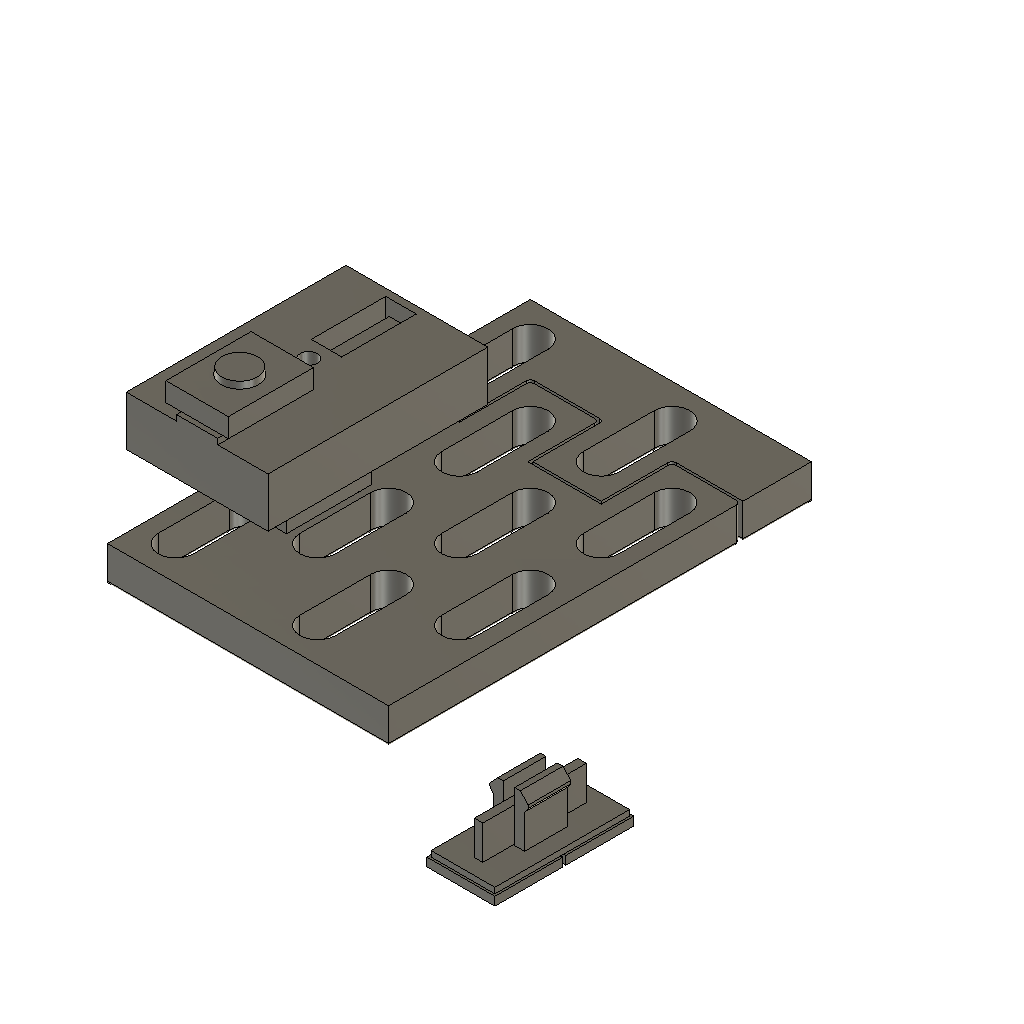
fit-kit-v06 (Autodesk Fusion 360 design; units mm, degrees)
part number: 2026-10-31-20-31-25-279
part number: 2026-10-31-20-31-25-627
part number: 2026-10-31-20-31-26-439
part number: 2026-10-31-20-31-27-406
part number: 2026-10-31-20-31-29-079
part number: 2026-10-31-20-31-30-945
part number: 2026-10-31-20-31-34-959
part number: 2026-10-31-20-31-37-328
part number: 2026-10-31-20-31-45-577
Autodesk Fusion 360 part; units mm, degrees
(part 1 of 2)
sketch "Mount coupon web sketch" plane through (0, 0, 0) normal (0, 0, 1) x (1, 0, 0) in component "Panel mounting coupon"
  line L0 (0.175, 0.175) -> (39.825, 0.175)
  line L1 (39.825, 0.175) -> (39.825, 39.825)
  line L2 (39.825, 39.825) -> (0.175, 39.825)
  line L3 (0.175, 39.825) -> (0.175, 0.175)
  dimension "d67" = 0.175
  dimension "d68" = 0.175
  dimension "d69" = 39.65
  dimension "d70" = 39.65
  constraint horizontal L0
  constraint vertical L1
  constraint horizontal L2
  constraint vertical L3
  measures "d67" horizontal distance of origin L0.start
  measures "d68" vertical distance of origin L0.start
  measures "d69" horizontal distance of L0.start L0.end
  measures "d70" vertical distance of L0.end L1.end
extrude "Mount coupon web" add sketch "Mount coupon web sketch" along normal blind 5 makes body 1 in component "Panel mounting coupon"
sketch "Whole slot seam tooth sketch" plane through (0, 0, 0) normal (0, 0, 1) x (1, 0, 0) in component "Panel mounting coupon"
  line L0 (10.175, 39) -> (19.825, 39)
  line L1 (19.825, 39) -> (19.825, 49.825)
  line L2 (19.825, 49.825) -> (10.175, 49.825)
  line L3 (10.175, 49.825) -> (10.175, 39)
  dimension "d73" = 10.175
  dimension "d74" = 39
  dimension "d75" = 9.65
  dimension "d76" = 10.825
  constraint horizontal L0
  constraint vertical L1
  constraint horizontal L2
  constraint vertical L3
  measures "d73" horizontal distance of origin L0.start
  measures "d74" vertical distance of origin L0.start
  measures "d75" horizontal distance of L0.start L0.end
  measures "d76" vertical distance of L0.end L1.end
extrude "Whole slot seam tooth" add sketch "Whole slot seam tooth sketch" along normal blind 5 bodies 1 in component "Panel mounting coupon"
fillet "Rounded tooth seed" radius 0.6 2 edges at (19.825, 49.825, 2.5) (10.175, 49.825, 2.5) on bodies 1 in component "Panel mounting coupon"
pattern_linear "Two teeth" count 2 spacing 20 along (1, 0, 0) of "Whole slot seam tooth", "Rounded tooth seed" in component "Panel mounting coupon"
sketch "A slots constrained seed" plane through (0, 0, 0) normal (0, 0, 1) x (1, 0, 0) in component "Panel mounting coupon"
  line L0 (7.5, 5) -> (7.5, 15)
  arc A0 (7.5, 15) -> (2.5, 15) centre (5, 15) ccw
  line L1 (2.5, 15) -> (2.5, 5)
  arc A1 (2.5, 5) -> (7.5, 5) centre (5, 5) ccw
  line L2 (5, 5) -> (5, 15) construction
  line L3 (5, 5) -> (15, 5) construction
  dimension "d85" = 5
  dimension "d86" = 10
  dimension "d87" = 90
  dimension "d88" = 10
  dimension "d89" = 5
  dimension "d90" = 5
  constraint tangent L0 A0
  constraint tangent A0 L1
  constraint tangent L1 A1
  constraint tangent L0 A1
  constraint parallel L0 L1
  constraint horizontal L3
  measures "d85" diameter of A0
  measures "d86" distance of A1.centre A0.centre
  measures "d87" angle of L2 L3
  measures "d88" horizontal distance of A1.centre L3.end
  measures "d89" horizontal distance of origin A1.centre
  measures "d90" vertical distance of origin A1.centre
extrude "A slots through cut" cut sketch "A slots constrained seed" along normal blind 5 bodies 1 in component "Panel mounting coupon"
pattern_linear "A slots lattice" count 2 spacing 20 along (1, 0, 0) count 2 spacing 20 along (0, 1, 0) of "A slots through cut" in component "Panel mounting coupon"
sketch "B slots including seam constrained seed" plane through (0, 0, 0) normal (0, 0, 1) x (1, 0, 0) in component "Panel mounting coupon"
  line L0 (17.5, 15) -> (17.5, 25)
  arc A0 (17.5, 25) -> (12.5, 25) centre (15, 25) ccw
  line L1 (12.5, 25) -> (12.5, 15)
  arc A1 (12.5, 15) -> (17.5, 15) centre (15, 15) ccw
  line L2 (15, 15) -> (15, 25) construction
  line L3 (15, 15) -> (25, 15) construction
  dimension "d97" = 5
  dimension "d98" = 10
  dimension "d99" = 90
  dimension "d100" = 10
  dimension "d101" = 15
  dimension "d102" = 15
  constraint tangent L0 A0
  constraint tangent A0 L1
  constraint tangent L1 A1
  constraint tangent L0 A1
  constraint parallel L0 L1
  constraint horizontal L3
  measures "d97" diameter of A0
  measures "d98" distance of A1.centre A0.centre
  measures "d99" angle of L2 L3
  measures "d100" horizontal distance of A1.centre L3.end
  measures "d101" horizontal distance of origin A1.centre
  measures "d102" vertical distance of origin A1.centre
extrude "B slots including seam through cut" cut sketch "B slots including seam constrained seed" along normal blind 5 bodies 1 in component "Panel mounting coupon"
pattern_linear "B slots including seam lattice" count 2 spacing 20 along (1, 0, 0) count 2 spacing 20 along (0, 1, 0) of "B slots including seam through cut" in component "Panel mounting coupon"
fillet "Production slot and perimeter rounding" radius 0.4 2 faces at (34.0461, 5.894, 0) (34.0461, 5.894, 0) on bodies 1 in component "Panel mounting coupon"
sketch "11 M2 through bore sketch" plane through (0, 0, 0) normal (0, 0, 1) x (1, 0, 0) in component "Panel mounting coupon"
  circle A0 centre (8.75, 20) radius 1.2
  dimension "d111" = 8.75
  dimension "d112" = 20
  dimension "d113" = 2.4
  measures "d111" horizontal distance of origin A0.centre
  measures "d112" vertical distance of origin A0.centre
  measures "d113" diameter of A0
extrude "11 M2 through bore" cut sketch "11 M2 through bore sketch" along normal blind 5 bodies 1 in component "Panel mounting coupon"
sketch "12 Flush countersink sketch" plane through (0, 0, 0) normal (0, 0, 1) x (1, 0, 0) in component "Panel mounting coupon"
  circle A0 centre (8.75, 20) radius 2
  dimension "d116" = 8.75
  dimension "d117" = 20
  dimension "d118" = 4
  measures "d116" horizontal distance of origin A0.centre
  measures "d117" vertical distance of origin A0.centre
  measures "d118" diameter of A0
extrude "12 Flush countersink" cut sketch "12 Flush countersink sketch" along normal blind 0.8 draft -45 bodies 1 in component "Panel mounting coupon"
ref_plane "WorkPlane1" through (0, 0, 5) normal (0, 0, 1) x (1, 0, 0) in component "Panel mounting coupon"
sketch "Blind rear production registration sketch" plane through (0, 0, 5) normal (0, 0, 1) x (1, 0, 0) in component "Panel mounting coupon"
  line L0 (8.4, 15.8) -> (11.6, 15.8)
  line L1 (11.6, 15.8) -> (11.6, 24.2)
  line L2 (11.6, 24.2) -> (8.4, 24.2)
  line L3 (8.4, 24.2) -> (8.4, 15.8)
  dimension "d123" = 8.4
  dimension "d124" = 15.8
  dimension "d125" = 3.2
  dimension "d126" = 8.4
  constraint horizontal L0
  constraint vertical L1
  constraint horizontal L2
  constraint vertical L3
  measures "d123" horizontal distance of origin L0.start
  measures "d124" vertical distance of origin L0.start
  measures "d125" horizontal distance of L0.start L0.end
  measures "d126" vertical distance of L0.end L1.end
extrude "Blind rear production registration" cut sketch "Blind rear production registration sketch" against normal blind 0.8 bodies 1 in component "Panel mounting coupon"
sketch "Small seam mate web sketch" plane through (0, 0, 0) normal (0, 0, 1) x (1, 0, 0) in component "PRINT seam mate"
  line L0 (0.175, 40.175) -> (39.825, 40.175)
  line L1 (39.825, 40.175) -> (39.825, 59.825)
  line L2 (39.825, 59.825) -> (0.175, 59.825)
  line L3 (0.175, 59.825) -> (0.175, 40.175)
  dimension "d129" = 0.175
  dimension "d130" = 40.175
  dimension "d131" = 39.65
  dimension "d132" = 19.65
  constraint horizontal L0
  constraint vertical L1
  constraint horizontal L2
  constraint vertical L3
  measures "d129" horizontal distance of origin L0.start
  measures "d130" vertical distance of origin L0.start
  measures "d131" horizontal distance of L0.start L0.end
  measures "d132" vertical distance of L0.end L1.end
extrude "Small seam mate web" add sketch "Small seam mate web sketch" along normal blind 5 separate body makes body 2 in component "PRINT seam mate"
sketch "Receiving step sketch" plane through (0, 0, 0) normal (0, 0, 1) x (1, 0, 0) in component "PRINT seam mate"
  line L0 (9.825, 39) -> (20.175, 39)
  line L1 (20.175, 39) -> (20.175, 50.175)
  line L2 (20.175, 50.175) -> (9.825, 50.175)
  line L3 (9.825, 50.175) -> (9.825, 39)
  dimension "d135" = 9.825
  dimension "d136" = 39
  dimension "d137" = 10.35
  dimension "d138" = 11.175
  constraint horizontal L0
  constraint vertical L1
  constraint horizontal L2
  constraint vertical L3
  measures "d135" horizontal distance of origin L0.start
  measures "d136" vertical distance of origin L0.start
  measures "d137" horizontal distance of L0.start L0.end
  measures "d138" vertical distance of L0.end L1.end
extrude "Receiving step" cut sketch "Receiving step sketch" along normal blind 5 bodies 2 in component "PRINT seam mate"
fillet "Rounded receiving step" radius 0.6 2 edges at (20.175, 50.175, 2.5) (9.825, 50.175, 2.5) on bodies 2 in component "PRINT seam mate"
sketch "Receiving step sketch (1)" plane through (0, 0, 0) normal (0, 0, 1) x (1, 0, 0) in component "PRINT seam mate"
  line L0 (29.825, 39) -> (40.175, 39)
  line L1 (40.175, 39) -> (40.175, 50.175)
  line L2 (40.175, 50.175) -> (29.825, 50.175)
  line L3 (29.825, 50.175) -> (29.825, 39)
  dimension "d143" = 29.825
  dimension "d144" = 39
  dimension "d145" = 10.35
  dimension "d146" = 11.175
  constraint horizontal L0
  constraint vertical L1
  constraint horizontal L2
  constraint vertical L3
  measures "d143" horizontal distance of origin L0.start
  measures "d144" vertical distance of origin L0.start
  measures "d145" horizontal distance of L0.start L0.end
  measures "d146" vertical distance of L0.end L1.end
extrude "Receiving step (1)" cut sketch "Receiving step sketch (1)" along normal blind 5 bodies 2 in component "PRINT seam mate"
fillet "Rounded receiving step (1)" radius 0.6 1 edges at (29.825, 50.175, 2.5) on bodies 2 in component "PRINT seam mate"
sketch "Whole A slots constrained seed" plane through (0, 0, 0) normal (0, 0, 1) x (1, 0, 0) in component "PRINT seam mate"
  line L0 (7.5, 45) -> (7.5, 55)
  arc A0 (7.5, 55) -> (2.5, 55) centre (5, 55) ccw
  line L1 (2.5, 55) -> (2.5, 45)
  arc A1 (2.5, 45) -> (7.5, 45) centre (5, 45) ccw
  line L2 (5, 45) -> (5, 55) construction
  line L3 (5, 45) -> (15, 45) construction
  dimension "d151" = 5
  dimension "d152" = 10
  dimension "d153" = 90
  dimension "d154" = 10
  dimension "d155" = 5
  dimension "d156" = 45
  constraint tangent L0 A0
  constraint tangent A0 L1
  constraint tangent L1 A1
  constraint tangent L0 A1
  constraint parallel L0 L1
  constraint horizontal L3
  measures "d151" diameter of A0
  measures "d152" distance of A1.centre A0.centre
  measures "d153" angle of L2 L3
  measures "d154" horizontal distance of A1.centre L3.end
  measures "d155" horizontal distance of origin A1.centre
  measures "d156" vertical distance of origin A1.centre
extrude "Whole A slots through cut" cut sketch "Whole A slots constrained seed" along normal blind 5 bodies 2 in component "PRINT seam mate"
pattern_linear "Whole A slots lattice" count 2 spacing 20 along (1, 0, 0) of "Whole A slots through cut" in component "PRINT seam mate"
fillet "Production slot and perimeter rounding'" radius 0.4 2 faces at (36.6917, 53.3917, 0) (36.6917, 53.3917, 0) on bodies 2 in component "PRINT seam mate"
ref_plane "WorkPlane1" through (0, 0, 15) normal (0, 0, 1) x (1, 0, 0) in component "PRINT carrier 00 single"
sketch "Carrier bearing block sketch" plane through (0, 0, 15) normal (0, 0, 1) x (1, 0, 0) in component "PRINT carrier 00 single"
  line L0 (0, 3) -> (20, 3)
  line L1 (20, 3) -> (20, 34)
  line L2 (20, 34) -> (0, 34)
  line L3 (0, 34) -> (0, 3)
  dimension "d167" = 3
  dimension "d168" = 20
  dimension "d169" = 31
  constraint horizontal L0
  constraint vertical L1
  constraint horizontal L2
  constraint vertical L3
  constraint vertical origin L0.start
  measures "d167" vertical distance of origin L0.start
  measures "d168" horizontal distance of L0.start L0.end
  measures "d169" vertical distance of L0.end L1.end
extrude "Carrier bearing block" add sketch "Carrier bearing block sketch" along normal blind 7 separate body makes body 3 in component "PRINT carrier 00 single"
ref_plane "WorkPlane2" through (0, 0, 15) normal (0, 0, 1) x (1, 0, 0) in component "PRINT carrier 00 single"
sketch "Integrated compression blade sketch" plane through (0, 0, 15) normal (0, 0, 1) x (1, 0, 0) in component "PRINT carrier 00 single"
  line L0 (8.4, 14) -> (11.6, 14)
  line L1 (11.6, 14) -> (11.6, 26)
  line L2 (11.6, 26) -> (8.4, 26)
  line L3 (8.4, 26) -> (8.4, 14)
  dimension "d174" = 8.4
  dimension "d175" = 14
  dimension "d176" = 3.2
  dimension "d177" = 12
  constraint horizontal L0
  constraint vertical L1
  constraint horizontal L2
  constraint vertical L3
  measures "d174" horizontal distance of origin L0.start
  measures "d175" vertical distance of origin L0.start
  measures "d176" horizontal distance of L0.start L0.end
  measures "d177" vertical distance of L0.end L1.end
extrude "Integrated compression blade" add sketch "Integrated compression blade sketch" against normal blind 10 bodies 3 in component "PRINT carrier 00 single"
ref_plane "WorkPlane3" through (0, 0, 5) normal (0, 0, 1) x (1, 0, 0) in component "PRINT carrier 00 single"
sketch "Axially releasing registration tongue sketch" plane through (0, 0, 5) normal (0, 0, 1) x (1, 0, 0) in component "PRINT carrier 00 single"
  line L0 (8.6, 16) -> (11.4, 16)
  line L1 (11.4, 16) -> (11.4, 24)
  line L2 (11.4, 24) -> (8.6, 24)
  line L3 (8.6, 24) -> (8.6, 16)
  dimension "d182" = 8.6
  dimension "d183" = 16
  dimension "d184" = 2.8
  dimension "d185" = 8
  constraint horizontal L0
  constraint vertical L1
  constraint horizontal L2
  constraint vertical L3
  measures "d182" horizontal distance of origin L0.start
  measures "d183" vertical distance of origin L0.start
  measures "d184" horizontal distance of L0.start L0.end
  measures "d185" vertical distance of L0.end L1.end
extrude "Axially releasing registration tongue" add sketch "Axially releasing registration tongue sketch" against normal blind 0.6 bodies 3 in component "PRINT carrier 00 single"
ref_plane "WorkPlane4" through (0, 0, 4.4) normal (0, 0, 1) x (1, 0, 0) in component "PRINT carrier 00 single"
sketch "Split registration into printable end pads sketch" plane through (0, 0, 4.4) normal (0, 0, 1) x (1, 0, 0) in component "PRINT carrier 00 single"
  line L0 (8.6, 18) -> (11.4, 18)
  line L1 (11.4, 18) -> (11.4, 22)
  line L2 (11.4, 22) -> (8.6, 22)
  line L3 (8.6, 22) -> (8.6, 18)
  dimension "d190" = 8.6
  dimension "d191" = 18
  dimension "d192" = 2.8
  dimension "d193" = 4
  constraint horizontal L0
  constraint vertical L1
  constraint horizontal L2
  constraint vertical L3
  measures "d190" horizontal distance of origin L0.start
  measures "d191" vertical distance of origin L0.start
  measures "d192" horizontal distance of L0.start L0.end
  measures "d193" vertical distance of L0.end L1.end
extrude "Split registration into printable end pads" cut sketch "Split registration into printable end pads sketch" along normal blind 0.6 bodies 3 in component "PRINT carrier 00 single"
ref_plane "WorkPlane5" through (0, 0, 4.4) normal (0, 0, 1) x (1, 0, 0) in component "PRINT carrier 00 single"
sketch "M2 through passage sketch" plane through (0, 0, 4.4) normal (0, 0, 1) x (1, 0, 0) in component "PRINT carrier 00 single"
  circle A0 centre (8.75, 20) radius 1.2
  dimension "d198" = 8.75
  dimension "d199" = 20
  dimension "d200" = 2.4
  measures "d198" horizontal distance of origin A0.centre
  measures "d199" vertical distance of origin A0.centre
  measures "d200" diameter of A0
extrude "M2 through passage" cut sketch "M2 through passage sketch" along normal blind 17.6 bodies 3 in component "PRINT carrier 00 single"
ref_plane "WorkPlane6" through (0, 0, 17) normal (0, 0, 1) x (1, 0, 0) in component "PRINT carrier 00 single"
sketch "Top-loaded captive hex nut track sketch" plane through (0, 0, 17) normal (0, 0, 1) x (1, 0, 0) in component "PRINT carrier 00 single"
  line L0 (6.6, 17.6) -> (10.9, 17.6)
  line L1 (10.9, 17.6) -> (10.9, 34)
  line L2 (10.9, 34) -> (6.6, 34)
  line L3 (6.6, 34) -> (6.6, 17.6)
  dimension "d205" = 6.6
  dimension "d206" = 17.6
  dimension "d207" = 4.3
  dimension "d208" = 16.4
  constraint horizontal L0
  constraint vertical L1
  constraint horizontal L2
  constraint vertical L3
  measures "d205" horizontal distance of origin L0.start
  measures "d206" vertical distance of origin L0.start
  measures "d207" horizontal distance of L0.start L0.end
  measures "d208" vertical distance of L0.end L1.end
extrude "Top-loaded captive hex nut track" cut sketch "Top-loaded captive hex nut track sketch" along normal blind 2 bodies 3 in component "PRINT carrier 00 single"
ref_plane "WorkPlane1" through (0, 0, 17.2) normal (0, 0, 1) x (1, 0, 0) in component "METAL M2 nut 000"
sketch "M2 hex nut AF4 envelope sketch" plane through (0, 0, 17.2) normal (0, 0, 1) x (1, 0, 0) in component "METAL M2 nut 000"
  line L0 (10.75, 21.1547) -> (8.75, 22.3094)
  line L1 (8.75, 22.3094) -> (6.75, 21.1547)
  line L2 (6.75, 21.1547) -> (6.75, 18.8453)
  line L3 (6.75, 18.8453) -> (8.75, 17.6906)
  line L4 (8.75, 17.6906) -> (10.75, 18.8453)
  line L5 (10.75, 18.8453) -> (10.75, 21.1547)
  dimension "d213" = 10.75
  dimension "d214" = 21.1547
  dimension "d215" = 8.75
  dimension "d216" = 22.3094
  dimension "d217" = 6.75
  dimension "d218" = 18.8453
  dimension "d219" = 8.75
  dimension "d220" = 17.6906
  constraint horizontal L0.start L1.end
  constraint vertical L1.end L2.end
  constraint vertical L0.start L4.end
  constraint horizontal L2.end L4.end
  measures "d213" horizontal distance of origin L0.start
  measures "d214" vertical distance of origin L0.start
  measures "d215" horizontal distance of origin L0.end
  measures "d216" vertical distance of origin L0.end
  measures "d217" horizontal distance of origin L1.end
  measures "d218" vertical distance of origin L2.end
  measures "d219" horizontal distance of origin L3.end
  measures "d220" vertical distance of origin L3.end
extrude "M2 hex nut AF4 envelope" add sketch "M2 hex nut AF4 envelope sketch" along normal blind 1.6 separate body makes body 4 in component "METAL M2 nut 000"
ref_plane "WorkPlane2" through (0, 0, 17.2) normal (0, 0, 1) x (1, 0, 0) in component "METAL M2 nut 000"
sketch "Thread envelope sketch" plane through (0, 0, 17.2) normal (0, 0, 1) x (1, 0, 0) in component "METAL M2 nut 000"
  circle A0 centre (8.75, 20) radius 1.05
  dimension "d225" = 8.75
  dimension "d226" = 20
  dimension "d227" = 2.1
  measures "d225" horizontal distance of origin A0.centre
  measures "d226" vertical distance of origin A0.centre
  measures "d227" diameter of A0
extrude "Thread envelope" cut sketch "Thread envelope sketch" along normal blind 1.6 bodies 4 in component "METAL M2 nut 000"
ref_plane "WorkPlane1" through (0, 0, 0.1) normal (0, 0, 1) x (1, 0, 0) in component "REFERENCE panel M2x20 000"
sketch "Nominal 90 degree head sketch" plane through (0, 0, 0.1) normal (0, 0, 1) x (1, 0, 0) in component "REFERENCE panel M2x20 000"
  circle A0 centre (8.75, 20) radius 1.9
  dimension "d248" = 8.75
  dimension "d249" = 20
  dimension "d250" = 3.8
  measures "d248" horizontal distance of origin A0.centre
  measures "d249" vertical distance of origin A0.centre
  measures "d250" diameter of A0
extrude "Nominal 90 degree head" add sketch "Nominal 90 degree head sketch" along normal blind 0.9 draft -45 separate body makes body 5 in component "REFERENCE panel M2x20 000"
ref_plane "WorkPlane2" through (0, 0, 1) normal (0, 0, 1) x (1, 0, 0) in component "REFERENCE panel M2x20 000"
sketch "Unthreaded major-diameter envelope sketch" plane through (0, 0, 1) normal (0, 0, 1) x (1, 0, 0) in component "REFERENCE panel M2x20 000"
  circle A0 centre (8.75, 20) radius 1
  dimension "d255" = 8.75
  dimension "d256" = 20
  dimension "d257" = 2
  measures "d255" horizontal distance of origin A0.centre
  measures "d256" vertical distance of origin A0.centre
  measures "d257" diameter of A0
extrude "Unthreaded major-diameter envelope" add sketch "Unthreaded major-diameter envelope sketch" along normal blind 19.1 bodies 5 in component "REFERENCE panel M2x20 000"
ref_plane "WorkPlane3" through (0, 0, 0.1) normal (0, 0, 1) x (1, 0, 0) in component "REFERENCE panel M2x20 000"
sketch "Cross drive envelope sketch" plane through (0, 0, 0.1) normal (0, 0, 1) x (1, 0, 0) in component "REFERENCE panel M2x20 000"
  line L0 (8.475, 18.86) -> (9.025, 18.86)
  line L1 (9.025, 18.86) -> (9.025, 21.14)
  line L2 (9.025, 21.14) -> (8.475, 21.14)
  line L3 (8.475, 21.14) -> (8.475, 18.86)
  dimension "d262" = 8.475
  dimension "d263" = 18.86
  dimension "d264" = 0.55
  dimension "d265" = 2.28
  constraint horizontal L0
  constraint vertical L1
  constraint horizontal L2
  constraint vertical L3
  measures "d262" horizontal distance of origin L0.start
  measures "d263" vertical distance of origin L0.start
  measures "d264" horizontal distance of L0.start L0.end
  measures "d265" vertical distance of L0.end L1.end
extrude "Cross drive envelope" cut sketch "Cross drive envelope sketch" along normal blind 0.35 bodies 5 in component "REFERENCE panel M2x20 000"
ref_plane "WorkPlane4" through (0, 0, 0.1) normal (0, 0, 1) x (1, 0, 0) in component "REFERENCE panel M2x20 000"
sketch "Cross drive envelope sketch (1)" plane through (0, 0, 0.1) normal (0, 0, 1) x (1, 0, 0) in component "REFERENCE panel M2x20 000"
  line L0 (7.61, 19.725) -> (9.89, 19.725)
  line L1 (9.89, 19.725) -> (9.89, 20.275)
  line L2 (9.89, 20.275) -> (7.61, 20.275)
  line L3 (7.61, 20.275) -> (7.61, 19.725)
  dimension "d270" = 7.61
  dimension "d271" = 19.725
  dimension "d272" = 2.28
  dimension "d273" = 0.55
  constraint horizontal L0
  constraint vertical L1
  constraint horizontal L2
  constraint vertical L3
  measures "d270" horizontal distance of origin L0.start
  measures "d271" vertical distance of origin L0.start
  measures "d272" horizontal distance of L0.start L0.end
  measures "d273" vertical distance of L0.end L1.end
extrude "Cross drive envelope (1)" cut sketch "Cross drive envelope sketch (1)" along normal blind 0.35 bodies 5 in component "REFERENCE panel M2x20 000"
ref_plane "WorkPlane7" through (0, 0, 22) normal (0, 0, 1) x (1, 0, 0) in component "PRINT carrier 00 single"
sketch "Extrusion mouth anti-rotation key sketch" plane through (0, 0, 22) normal (0, 0, 1) x (1, 0, 0) in component "PRINT carrier 00 single"
  line L0 (7.1, 3) -> (12.9, 3)
  line L1 (12.9, 3) -> (12.9, 5)
  line L2 (12.9, 5) -> (7.1, 5)
  line L3 (7.1, 5) -> (7.1, 3)
  dimension "d278" = 7.1
  dimension "d279" = 3
  dimension "d280" = 5.8
  dimension "d281" = 2
  constraint horizontal L0
  constraint vertical L1
  constraint horizontal L2
  constraint vertical L3
  measures "d278" horizontal distance of origin L0.start
  measures "d279" vertical distance of origin L0.start
  measures "d280" horizontal distance of L0.start L0.end
  measures "d281" vertical distance of L0.end L1.end
extrude "Extrusion mouth anti-rotation key" add sketch "Extrusion mouth anti-rotation key sketch" along normal blind 0.8 bodies 3 in component "PRINT carrier 00 single"
ref_plane "WorkPlane8" through (0, 0, 22) normal (0, 0, 1) x (1, 0, 0) in component "PRINT carrier 00 single"
sketch "Extrusion mouth anti-rotation key sketch (1)" plane through (0, 0, 22) normal (0, 0, 1) x (1, 0, 0) in component "PRINT carrier 00 single"
  line L0 (7.1, 13) -> (12.9, 13)
  line L1 (12.9, 13) -> (12.9, 15)
  line L2 (12.9, 15) -> (7.1, 15)
  line L3 (7.1, 15) -> (7.1, 13)
  dimension "d286" = 7.1
  dimension "d287" = 13
  dimension "d288" = 5.8
  dimension "d289" = 2
  constraint horizontal L0
  constraint vertical L1
  constraint horizontal L2
  constraint vertical L3
  measures "d286" horizontal distance of origin L0.start
  measures "d287" vertical distance of origin L0.start
  measures "d288" horizontal distance of L0.start L0.end
  measures "d289" vertical distance of L0.end L1.end
extrude "Extrusion mouth anti-rotation key (1)" add sketch "Extrusion mouth anti-rotation key sketch (1)" along normal blind 0.8 bodies 3 in component "PRINT carrier 00 single"
ref_plane "WorkPlane9" through (0, 0, 15) normal (0, 0, 1) x (1, 0, 0) in component "PRINT carrier 00 single"
sketch "Carrier M5 bore sketch" plane through (0, 0, 15) normal (0, 0, 1) x (1, 0, 0) in component "PRINT carrier 00 single"
  circle A0 centre (10, 9) radius 2.75
  dimension "d294" = 10
  dimension "d295" = 9
  dimension "d296" = 5.5
  measures "d294" horizontal distance of origin A0.centre
  measures "d295" vertical distance of origin A0.centre
  measures "d296" diameter of A0
extrude "Carrier M5 bore" cut sketch "Carrier M5 bore sketch" along normal blind 7 bodies 3 in component "PRINT carrier 00 single"
ref_plane "WorkPlane10" through (0, 0, 15) normal (0, 0, 1) x (1, 0, 0) in component "PRINT carrier 00 single"
sketch "Recessed carrier fixing sketch" plane through (0, 0, 15) normal (0, 0, 1) x (1, 0, 0) in component "PRINT carrier 00 single"
  circle A0 centre (10, 9) radius 4.7
  dimension "d301" = 10
  dimension "d302" = 9
  dimension "d303" = 9.4
  measures "d301" horizontal distance of origin A0.centre
  measures "d302" vertical distance of origin A0.centre
  measures "d303" diameter of A0
extrude "Recessed carrier fixing" cut sketch "Recessed carrier fixing sketch" along normal blind 1.95 draft -45 bodies 3 in component "PRINT carrier 00 single"
ref_plane "WorkPlane1" through (0, 0, 15.1) normal (0, 0, 1) x (1, 0, 0) in component "REFERENCE carrier M5x12 00"
sketch "Nominal 90 degree head sketch (2)" plane through (0, 0, 15.1) normal (0, 0, 1) x (1, 0, 0) in component "REFERENCE carrier M5x12 00"
  circle A0 centre (10, 9) radius 4.6
  dimension "d308" = 10
  dimension "d309" = 9
  dimension "d310" = 9.2
  measures "d308" horizontal distance of origin A0.centre
  measures "d309" vertical distance of origin A0.centre
  measures "d310" diameter of A0
extrude "Nominal 90 degree head'" add sketch "Nominal 90 degree head sketch (2)" along normal blind 2.1 draft -45 separate body makes body 6 in component "REFERENCE carrier M5x12 00"
ref_plane "WorkPlane2" through (0, 0, 17.2) normal (0, 0, 1) x (1, 0, 0) in component "REFERENCE carrier M5x12 00"
sketch "Unthreaded major-diameter envelope sketch (2)" plane through (0, 0, 17.2) normal (0, 0, 1) x (1, 0, 0) in component "REFERENCE carrier M5x12 00"
  circle A0 centre (10, 9) radius 2.5
  dimension "d315" = 10
  dimension "d316" = 9
  dimension "d317" = 5
  measures "d315" horizontal distance of origin A0.centre
  measures "d316" vertical distance of origin A0.centre
  measures "d317" diameter of A0
extrude "Unthreaded major-diameter envelope'" add sketch "Unthreaded major-diameter envelope sketch (2)" along normal blind 9.9 bodies 6 in component "REFERENCE carrier M5x12 00"
ref_plane "WorkPlane3" through (0, 0, 15.1) normal (0, 0, 1) x (1, 0, 0) in component "REFERENCE carrier M5x12 00"
sketch "Cross drive envelope sketch (2)" plane through (0, 0, 15.1) normal (0, 0, 1) x (1, 0, 0) in component "REFERENCE carrier M5x12 00"
  line L0 (9.725, 6.24) -> (10.275, 6.24)
  line L1 (10.275, 6.24) -> (10.275, 11.76)
  line L2 (10.275, 11.76) -> (9.725, 11.76)
  line L3 (9.725, 11.76) -> (9.725, 6.24)
  dimension "d322" = 9.725
  dimension "d323" = 6.24
  dimension "d324" = 0.55
  dimension "d325" = 5.52
  constraint horizontal L0
  constraint vertical L1
  constraint horizontal L2
  constraint vertical L3
  measures "d322" horizontal distance of origin L0.start
  measures "d323" vertical distance of origin L0.start
  measures "d324" horizontal distance of L0.start L0.end
  measures "d325" vertical distance of L0.end L1.end
extrude "Cross drive envelope'" cut sketch "Cross drive envelope sketch (2)" along normal blind 0.35 bodies 6 in component "REFERENCE carrier M5x12 00"
ref_plane "WorkPlane4" through (0, 0, 15.1) normal (0, 0, 1) x (1, 0, 0) in component "REFERENCE carrier M5x12 00"
sketch "Cross drive envelope sketch (1) (2)" plane through (0, 0, 15.1) normal (0, 0, 1) x (1, 0, 0) in component "REFERENCE carrier M5x12 00"
  line L0 (7.24, 8.725) -> (12.76, 8.725)
  line L1 (12.76, 8.725) -> (12.76, 9.275)
  line L2 (12.76, 9.275) -> (7.24, 9.275)
  line L3 (7.24, 9.275) -> (7.24, 8.725)
  dimension "d330" = 7.24
  dimension "d331" = 8.725
  dimension "d332" = 5.52
  dimension "d333" = 0.55
  constraint horizontal L0
  constraint vertical L1
  constraint horizontal L2
  constraint vertical L3
  measures "d330" horizontal distance of origin L0.start
  measures "d331" vertical distance of origin L0.start
  measures "d332" horizontal distance of L0.start L0.end
  measures "d333" vertical distance of L0.end L1.end
extrude "Cross drive envelope (1)'" cut sketch "Cross drive envelope sketch (1) (2)" along normal blind 0.35 bodies 6 in component "REFERENCE carrier M5x12 00"
ref_plane "WorkPlane1" through (0, 0, 23.5) normal (0, 0, 1) x (1, 0, 0) in component "METAL channel nut 00"
sketch "Provisional metal channel nut sketch" plane through (0, 0, 23.5) normal (0, 0, 1) x (1, 0, 0) in component "METAL channel nut 00"
  line L0 (5.6, 3) -> (14.4, 3)
  line L1 (14.4, 3) -> (14.4, 15)
  line L2 (14.4, 15) -> (5.6, 15)
  line L3 (5.6, 15) -> (5.6, 3)
  dimension "d338" = 5.6
  dimension "d339" = 3
  dimension "d340" = 8.8
  dimension "d341" = 12
  constraint horizontal L0
  constraint vertical L1
  constraint horizontal L2
  constraint vertical L3
  measures "d338" horizontal distance of origin L0.start
  measures "d339" vertical distance of origin L0.start
  measures "d340" horizontal distance of L0.start L0.end
  measures "d341" vertical distance of L0.end L1.end
extrude "Provisional metal channel nut" add sketch "Provisional metal channel nut sketch" along normal blind 2.7 separate body makes body 7 in component "METAL channel nut 00"
ref_plane "WorkPlane2" through (0, 0, 23.5) normal (0, 0, 1) x (1, 0, 0) in component "METAL channel nut 00"
sketch "Thread envelope sketch (2)" plane through (0, 0, 23.5) normal (0, 0, 1) x (1, 0, 0) in component "METAL channel nut 00"
  circle A0 centre (10, 9) radius 2.6
  dimension "d346" = 10
  dimension "d347" = 9
  dimension "d348" = 5.2
  measures "d346" horizontal distance of origin A0.centre
  measures "d347" vertical distance of origin A0.centre
  measures "d348" diameter of A0
extrude "Thread envelope'" cut sketch "Thread envelope sketch (2)" along normal blind 2.7 bodies 7 in component "METAL channel nut 00"
ref_plane "WorkPlane11" through (0, 0, 19) normal (0, 0, 1) x (1, 0, 0) in component "PRINT carrier 00 single"
sketch "Release free end of nut-retaining spring sketch" plane through (0, 0, 19) normal (0, 0, 1) x (1, 0, 0) in component "PRINT carrier 00 single"
  line L0 (6.6, 22.5) -> (10.9, 22.5)
  line L1 (10.9, 22.5) -> (10.9, 23)
  line L2 (10.9, 23) -> (6.6, 23)
  line L3 (6.6, 23) -> (6.6, 22.5)
  dimension "d353" = 6.6
  dimension "d354" = 22.5
  dimension "d355" = 4.3
  dimension "d356" = 0.5
  constraint horizontal L0
  constraint vertical L1
  constraint horizontal L2
  constraint vertical L3
  measures "d353" horizontal distance of origin L0.start
  measures "d354" vertical distance of origin L0.start
  measures "d355" horizontal distance of L0.start L0.end
  measures "d356" vertical distance of L0.end L1.end
extrude "Release free end of nut-retaining spring" cut sketch "Release free end of nut-retaining spring sketch" along normal blind 3 bodies 3 in component "PRINT carrier 00 single"
ref_plane "WorkPlane12" through (0, 0, 19.8) normal (0, 0, 1) x (1, 0, 0) in component "PRINT carrier 00 single"
sketch "Nut spring deflection space sketch" plane through (0, 0, 19.8) normal (0, 0, 1) x (1, 0, 0) in component "PRINT carrier 00 single"
  line L0 (6.6, 23) -> (10.9, 23)
  line L1 (10.9, 23) -> (10.9, 33)
  line L2 (10.9, 33) -> (6.6, 33)
  line L3 (6.6, 33) -> (6.6, 23)
  dimension "d361" = 6.6
  dimension "d362" = 23
  dimension "d363" = 4.3
  dimension "d364" = 10
  constraint horizontal L0
  constraint vertical L1
  constraint horizontal L2
  constraint vertical L3
  measures "d361" horizontal distance of origin L0.start
  measures "d362" vertical distance of origin L0.start
  measures "d363" horizontal distance of L0.start L0.end
  measures "d364" vertical distance of L0.end L1.end
extrude "Nut spring deflection space" cut sketch "Nut spring deflection space sketch" along normal blind 2.2 bodies 3 in component "PRINT carrier 00 single"
ref_plane "WorkPlane13" through (0, 0, 19) normal (0, 0, 1) x (1, 0, 0) in component "PRINT carrier 00 single"
sketch "Nut spring side relief sketch" plane through (0, 0, 19) normal (0, 0, 1) x (1, 0, 0) in component "PRINT carrier 00 single"
  line L0 (6.6, 23) -> (7.1, 23)
  line L1 (7.1, 23) -> (7.1, 33)
  line L2 (7.1, 33) -> (6.6, 33)
  line L3 (6.6, 33) -> (6.6, 23)
  dimension "d369" = 6.6
  dimension "d370" = 23
  dimension "d371" = 0.5
  dimension "d372" = 10
  constraint horizontal L0
  constraint vertical L1
  constraint horizontal L2
  constraint vertical L3
  measures "d369" horizontal distance of origin L0.start
  measures "d370" vertical distance of origin L0.start
  measures "d371" horizontal distance of L0.start L0.end
  measures "d372" vertical distance of L0.end L1.end
extrude "Nut spring side relief" cut sketch "Nut spring side relief sketch" along normal blind 0.8 bodies 3 in component "PRINT carrier 00 single"
ref_plane "WorkPlane14" through (0, 0, 19) normal (0, 0, 1) x (1, 0, 0) in component "PRINT carrier 00 single"
sketch "Nut spring side relief sketch (1)" plane through (0, 0, 19) normal (0, 0, 1) x (1, 0, 0) in component "PRINT carrier 00 single"
  line L0 (10.4, 23) -> (10.9, 23)
  line L1 (10.9, 23) -> (10.9, 33)
  line L2 (10.9, 33) -> (10.4, 33)
  line L3 (10.4, 33) -> (10.4, 23)
  dimension "d377" = 10.4
  dimension "d378" = 23
  dimension "d379" = 0.5
  dimension "d380" = 10
  constraint horizontal L0
  constraint vertical L1
  constraint horizontal L2
  constraint vertical L3
  measures "d377" horizontal distance of origin L0.start
  measures "d378" vertical distance of origin L0.start
  measures "d379" horizontal distance of L0.start L0.end
  measures "d380" vertical distance of L0.end L1.end
extrude "Nut spring side relief (1)" cut sketch "Nut spring side relief sketch (1)" along normal blind 0.8 bodies 3 in component "PRINT carrier 00 single"
ref_plane "WorkPlane15" through (7.1, 0, 0) normal (1, 0, 0) x (0, 1, 0) in component "PRINT carrier 00 single"
sketch "Integral nut retaining ramp - flex test required sketch" plane through (7.1, 0, 0) normal (1, 0, 0) x (0, 0, -1) in component "PRINT carrier 00 single"
  line L0 (-19.2, 23) -> (-19.2, 24.6)
  line L1 (-19.2, 24.6) -> (-17.8, 23.8)
  line L2 (-17.8, 23.8) -> (-17.8, 23)
  line L3 (-17.8, 23) -> (-19.2, 23)
  dimension "d385" = 19.2
  dimension "d386" = 23
  dimension "d387" = 24.6
  dimension "d388" = 17.8
  dimension "d389" = 23.8
  constraint vertical L0.start L0.end
  constraint vertical L1.end L2.end
  constraint horizontal L0.start L2.end
  measures "d385" horizontal distance of origin L0.start
  measures "d386" vertical distance of origin L0.start
  measures "d387" vertical distance of origin L0.end
  measures "d388" horizontal distance of origin L1.end
  measures "d389" vertical distance of origin L1.end
extrude "Integral nut retaining ramp - flex test required" add sketch "Integral nut retaining ramp - flex test required sketch" along normal blind 2.05 bodies 3 in component "PRINT carrier 00 single"
ref_plane "WorkPlane1" through (0, 0, -0.8) normal (0, 0, 1) x (1, 0, 0) in component "PRINT two pixel tile"
sketch "Tile core sketch" plane through (0, 0, -0.8) normal (0, 0, 1) x (1, 0, 0) in component "PRINT two pixel tile"
  line L0 (55.5, -9.5) -> (64.5, -9.5)
  line L1 (64.5, -9.5) -> (64.5, 9.5)
  line L2 (64.5, 9.5) -> (55.5, 9.5)
  line L3 (55.5, 9.5) -> (55.5, -9.5)
  dimension "d399" = 55.5
  dimension "d400" = 9.5
  dimension "d401" = 9
  dimension "d402" = 19
  constraint horizontal L0
  constraint vertical L1
  constraint horizontal L2
  constraint vertical L3
  measures "d399" horizontal distance of origin L0.start
  measures "d400" vertical distance of origin L0.start
  measures "d401" horizontal distance of L0.start L0.end
  measures "d402" vertical distance of L0.end L1.end
extrude "Tile core" add sketch "Tile core sketch" along normal blind 0.8 separate body makes body 8 in component "PRINT two pixel tile"
sketch "Gravity bearing spine sketch" plane through (0, 0, 0) normal (0, 0, 1) x (1, 0, 0) in component "PRINT two pixel tile"
  line L0 (59.4, -7.3) -> (60.6, -7.3)
  line L1 (60.6, -7.3) -> (60.6, 7.3)
  line L2 (60.6, 7.3) -> (59.4, 7.3)
  line L3 (59.4, 7.3) -> (59.4, -7.3)
  dimension "d405" = 59.4
  dimension "d406" = 7.3
  dimension "d407" = 1.2
  dimension "d408" = 14.6
  constraint horizontal L0
  constraint vertical L1
  constraint horizontal L2
  constraint vertical L3
  measures "d405" horizontal distance of origin L0.start
  measures "d406" vertical distance of origin L0.start
  measures "d407" horizontal distance of L0.start L0.end
  measures "d408" vertical distance of L0.end L1.end
extrude "Gravity bearing spine" add sketch "Gravity bearing spine sketch" along normal blind 4.8 bodies 8 in component "PRINT two pixel tile"
ref_plane "WorkPlane2" through (0, -3, 0) normal (0, 1, 0) x (0, 0, 1) in component "PRINT two pixel tile"
sketch "Mosaic spring -1 sketch" plane through (0, -3, 0) normal (0, 1, 0) x (1, 0, 0) in component "PRINT two pixel tile"
  line L0 (59.2, 0) -> (57.8, 0)
  line L1 (57.8, 0) -> (57.8, -4.8)
  line L2 (57.8, -4.8) -> (57.3, -5.5)
  line L3 (57.3, -5.5) -> (57.3, -5.9)
  line L4 (57.3, -5.9) -> (58.4, -7.1)
  line L5 (58.4, -7.1) -> (59.2, -7.1)
  line L6 (59.2, -7.1) -> (59.2, 0)
  dimension "d413" = 59.2
  dimension "d414" = 57.8
  dimension "d415" = 4.8
  dimension "d416" = 57.3
  dimension "d417" = 5.5
  dimension "d418" = 5.9
  dimension "d419" = 58.4
  dimension "d420" = 7.1
  constraint horizontal origin L0.start
  constraint horizontal L0.start L0.end
  constraint vertical L0.end L1.end
  constraint vertical L2.end L3.end
  constraint vertical L0.start L5.end
  constraint horizontal L4.end L5.end
  measures "d413" horizontal distance of origin L0.start
  measures "d414" horizontal distance of origin L0.end
  measures "d415" vertical distance of origin L1.end
  measures "d416" horizontal distance of origin L2.end
  measures "d417" vertical distance of origin L2.end
  measures "d418" vertical distance of origin L3.end
  measures "d419" horizontal distance of origin L4.end
  measures "d420" vertical distance of origin L4.end
extrude "Mosaic spring -1" add sketch "Mosaic spring -1 sketch" along normal blind 6 bodies 8 in component "PRINT two pixel tile"
ref_plane "WorkPlane3" through (0, -3, 0) normal (0, 1, 0) x (0, 0, 1) in component "PRINT two pixel tile"
sketch "Mosaic spring 1 sketch" plane through (0, -3, 0) normal (0, 1, 0) x (1, 0, 0) in component "PRINT two pixel tile"
  line L0 (60.8, 0) -> (62.2, 0)
  line L1 (62.2, 0) -> (62.2, -4.8)
  line L2 (62.2, -4.8) -> (62.7, -5.5)
  line L3 (62.7, -5.5) -> (62.7, -5.9)
  line L4 (62.7, -5.9) -> (61.6, -7.1)
  line L5 (61.6, -7.1) -> (60.8, -7.1)
  line L6 (60.8, -7.1) -> (60.8, 0)
  dimension "d425" = 60.8
  dimension "d426" = 62.2
  dimension "d427" = 4.8
  dimension "d428" = 62.7
  dimension "d429" = 5.5
  dimension "d430" = 5.9
  dimension "d431" = 61.6
  dimension "d432" = 7.1
  constraint horizontal origin L0.start
  constraint horizontal L0.start L0.end
  constraint vertical L0.end L1.end
  constraint vertical L2.end L3.end
  constraint vertical L0.start L5.end
  constraint horizontal L4.end L5.end
  measures "d425" horizontal distance of origin L0.start
  measures "d426" horizontal distance of origin L0.end
  measures "d427" vertical distance of origin L1.end
  measures "d428" horizontal distance of origin L2.end
  measures "d429" vertical distance of origin L2.end
  measures "d430" vertical distance of origin L3.end
  measures "d431" horizontal distance of origin L4.end
  measures "d432" vertical distance of origin L4.end
extrude "Mosaic spring 1" add sketch "Mosaic spring 1 sketch" along normal blind 6 bodies 8 in component "PRINT two pixel tile"
ref_plane "WorkPlane4" through (0, 0, -2) normal (0, 0, 1) x (1, 0, 0) in component "PRINT two pixel tile"
sketch "Pixel face sketch" plane through (0, 0, -2) normal (0, 0, 1) x (1, 0, 0) in component "PRINT two pixel tile"
  line L0 (55.2, -9.8) -> (64.8, -9.8)
  line L1 (64.8, -9.8) -> (64.8, -0.2)
  line L2 (64.8, -0.2) -> (55.2, -0.2)
  line L3 (55.2, -0.2) -> (55.2, -9.8)
  dimension "d437" = 55.2
  dimension "d438" = 9.8
  dimension "d439" = 9.6
  dimension "d440" = 9.6
  constraint horizontal L0
  constraint vertical L1
  constraint horizontal L2
  constraint vertical L3
  measures "d437" horizontal distance of origin L0.start
  measures "d438" vertical distance of origin L0.start
  measures "d439" horizontal distance of L0.start L0.end
  measures "d440" vertical distance of L0.end L1.end
extrude "Pixel face" add sketch "Pixel face sketch" along normal blind 1.2 bodies 8 in component "PRINT two pixel tile"
ref_plane "WorkPlane5" through (0, 0, -2) normal (0, 0, 1) x (1, 0, 0) in component "PRINT two pixel tile"
sketch "Pixel face sketch (1)" plane through (0, 0, -2) normal (0, 0, 1) x (1, 0, 0) in component "PRINT two pixel tile"
  line L0 (55.2, 0.2) -> (64.8, 0.2)
  line L1 (64.8, 0.2) -> (64.8, 9.8)
  line L2 (64.8, 9.8) -> (55.2, 9.8)
  line L3 (55.2, 9.8) -> (55.2, 0.2)
  dimension "d445" = 55.2
  dimension "d446" = 0.2
  dimension "d447" = 9.6
  dimension "d448" = 9.6
  constraint horizontal L0
  constraint vertical L1
  constraint horizontal L2
  constraint vertical L3
  measures "d445" horizontal distance of origin L0.start
  measures "d446" vertical distance of origin L0.start
  measures "d447" horizontal distance of L0.start L0.end
  measures "d448" vertical distance of L0.end L1.end
extrude "Pixel face (1)" add sketch "Pixel face sketch (1)" along normal blind 1.2 bodies 8 in component "PRINT two pixel tile"
component "Panel mounting coupon" placed x (1, 0, 0) y (0, 1, 0) z (0, 0, 1) at (0, 0, 0)
component "PRINT seam mate" placed x (1, 0, 0) y (0, 1, 0) z (0, 0, 1) at (0, 0, 0)
component "PRINT carrier 00 single" placed x (1, 0, 0) y (0, 1, 0) z (0, 0, 1) at (0, 0, 0)
component "METAL M2 nut 000" placed x (1, 0, 0) y (0, 1, 0) z (0, 0, 1) at (0, 0, 0)
component "REFERENCE panel M2x20 000" placed x (1, 0, 0) y (0, 1, 0) z (0, 0, 1) at (0, 0, 0)
component "REFERENCE carrier M5x12 00" placed x (1, 0, 0) y (0, 1, 0) z (0, 0, 1) at (0, 0, 0)
component "METAL channel nut 00" placed x (1, 0, 0) y (0, 1, 0) z (0, 0, 1) at (0, 0, 0)
component "PRINT two pixel tile" placed x (1, 0, 0) y (0, 1, 0) z (0, 0, 1) at (0, 0, 0)
equation "columns = 2" comment "Even integer 4..14; each cell is 20 mm"
equation "rows = 2" comment "Even integer 4..14"
equation "pitch = 20 mm" comment "Keep for dense SKADIS compatible lattice"
equation "panelWidth = columns * pitch" comment "Nominal module pitch X"
equation "panelHeight = rows * pitch" comment "Nominal module pitch Y"
equation "seamGap = 0.35 mm" comment "Physical envelope shrinks around fixed lattice"
equation "boardThickness = 5 mm" comment "Fit-test with real hooks"
equation "slotWidth = 5 mm" comment "Minimum throat width"
equation "slotHeight = 15 mm" comment "Minimum throat height"
equation "entryRadius = 0.4 mm" comment "Front slot and perimeter edge rounding"
equation "cornerRadius = 6 mm" comment "Plan-view panel corner rounding"
equation "hookClearance = 10 mm" comment "PROVISIONAL unobstructed depth behind board; carriers begin at its rear boundary"
equation "frameZ = carrierZ + carrierThickness" comment "Front extrusion datum"
equation "profileMouth = 6.28 mm" comment "User measured mouth"
equation "profileCavity = 11 mm" comment "User measured widest cavity"
equation "profileDepth = 6.2 mm" comment "User measured face-to-floor depth"
equation "profileFloor = 5.7 mm" comment "User estimate, lower confidence"
equation "profileLip = 1.5 mm" comment "Unmeasured; tentative comparable catalog value"
equation "profileTaperStart = profileDepth - ( profileCavity - profileFloor ) / 2" comment "Assumed 45-degree inner slopes"
equation "profileBore = 5 mm" comment "Unmeasured central bore, reference only"
equation "nutWidth = 8.8 mm" comment "Provisional low-profile METAL T-nut envelope, not old rectangular carrier"
equation "nutLength = 12 mm" comment "End-loaded anti-rotation metal nut envelope"
equation "nutThickness = 2.7 mm" comment "Thin nut reference; fit/load still unverified"
equation "jointLeg = 18 mm" comment "In-bay angle footprint"
equation "jointThickness = 3 mm" comment "Metal bracket thickness"
equation "jointDepth = 16 mm" comment "Bracket depth within 20 mm rail"
equation "sideScrewLength = 8 mm" comment "M5x8 reference; check against actual bracket and nut"
equation "wallTabHeight = 24 mm" comment "Tab along extrusion"
equation "wallTabReach = 22 mm" comment "Tab into open bay"
equation "wallAnchorClearance = 6.5 mm" comment "Placeholder wall anchor interface"
equation "wallDriverDiameter = 12 mm" comment "Clear tool envelope in open bays"
equation "keyDriverDiameter = 5 mm" comment "Short hex-key working-leg envelope"
equation "keyDriverReach = 20 mm" comment "Short hex-key working-leg reach"
equation "supportWidth = 3.2 mm" comment "Prototype blade; two perimeter lines need print review"
equation "supportLength = 12 mm" comment "Compression bearing length"
equation "hookEnvelopeWidth = 6 mm" comment "Conservative provisional continuous hook column"
equation "carrierThickness = 7 mm" comment "Room for captive M2 nut and stock M5x12"
equation "panelClearance = 2.4 mm" comment "M2 clearance"
equation "panelHeadPocket = 4 mm" comment "DIN965 3.8 mm head plus 0.1 mm recess"
equation "carrierHeadPocket = 9.4 mm" comment "DIN965 M5 9.2 mm head plus recess"
equation "carrierBore = 5.5 mm" comment "M5 clearance"
equation "tongueWidth = 2.8 mm" comment "Rear axial registration tongue"
equation "tongueLength = 8 mm" comment "Axial release registration"
equation "tongueDepth = 0.6 mm" comment "Tongue engagement"
equation "registerClearance = 0.2 mm" comment "Each side of printed tongue"
equation "carrierZ = boardThickness + hookClearance" comment "Rear hook cavity boundary"
equation "stepCorner = 0.6 mm" comment "Small plan corner relief; printed fit remains untested"
equation "d67 = abs(seamGap / 2)"
equation "d68 = abs(seamGap / 2)"
equation "d69 = 2 * pitch - seamGap"
equation "d70 = 2 * pitch - seamGap"
equation "d71 = boardThickness"
equation "d73 = abs(pitch / 2 + seamGap / 2)"
equation "d74 = abs(2 * pitch - 1 mm)"
equation "d75 = pitch / 2 - seamGap"
equation "d76 = pitch / 2 + 1 mm - seamGap / 2"
equation "d77 = boardThickness"
equation "d80 = stepCorner"
equation "d81 = columns"
equation "d83 = pitch"
equation "d84 = pitch"
equation "d85 = slotWidth"
equation "d86 = slotHeight - slotWidth"
equation "d88 = pitch / 2"
equation "d89 = abs(pitch / 4)"
equation "d90 = abs(( pitch / 2 ) - ( slotHeight - slotWidth ) / 2)"
equation "d91 = boardThickness"
equation "d95 = pitch"
equation "d96 = pitch"
equation "d97 = slotWidth"
equation "d98 = slotHeight - slotWidth"
equation "d100 = pitch / 2"
equation "d101 = abs(3 * pitch / 4)"
equation "d102 = abs(( pitch ) - ( slotHeight - slotWidth ) / 2)"
equation "d103 = boardThickness"
equation "d107 = pitch"
equation "d108 = pitch"
equation "d110 = entryRadius"
equation "d111 = ( abs(pitch / 2) ) - webCenterOffset"
equation "d112 = abs(pitch)"
equation "d113 = panelClearance"
equation "d114 = boardThickness"
equation "d116 = ( abs(pitch / 2) ) - webCenterOffset"
equation "d117 = abs(pitch)"
equation "d118 = panelHeadPocket"
equation "d119 = ( panelHeadPocket - panelClearance ) / 2"
equation "d121 = boardThickness"
equation "d123 = abs(pitch / 2 - tongueWidth / 2 - registerClearance)"
equation "d124 = abs(pitch - tongueLength / 2 - registerClearance)"
equation "d125 = tongueWidth + 2 * registerClearance"
equation "d126 = tongueLength + 2 * registerClearance"
equation "d127 = -tongueDepth - 0.2 mm"
equation "d129 = abs(seamGap / 2)"
equation "d130 = abs(2 * pitch + seamGap / 2)"
equation "d131 = 2 * pitch - seamGap"
equation "d132 = pitch - seamGap"
equation "d133 = boardThickness"
equation "d135 = abs(pitch / 2 - seamGap / 2)"
equation "d136 = abs(2 * pitch - 1 mm)"
equation "d137 = pitch / 2 + seamGap"
equation "d138 = pitch / 2 + 1 mm + seamGap / 2"
equation "d139 = boardThickness"
equation "d142 = stepCorner"
equation "d143 = abs(3 * pitch / 2 - seamGap / 2)"
equation "d144 = abs(2 * pitch - 1 mm)"
equation "d145 = pitch / 2 + seamGap"
equation "d146 = pitch / 2 + 1 mm + seamGap / 2"
equation "d147 = boardThickness"
equation "d150 = stepCorner"
equation "d151 = slotWidth"
equation "d152 = slotHeight - slotWidth"
equation "d154 = pitch / 2"
equation "d155 = abs(pitch / 4)"
equation "d156 = abs(( 2 * pitch + pitch / 2 ) - ( slotHeight - slotWidth ) / 2)"
equation "d157 = boardThickness"
equation "d161 = pitch"
equation "d162 = pitch"
equation "d164 = entryRadius"
equation "d165 = carrierZ"
equation "d167 = abs(pitch - 17 mm)"
equation "d170 = carrierThickness"
equation "d172 = carrierZ"
equation "d174 = abs(pitch / 2 - supportWidth / 2)"
equation "d175 = abs(pitch - supportLength / 2)"
equation "d176 = supportWidth"
equation "d177 = supportLength"
equation "d178 = -hookClearance"
equation "d180 = boardThickness"